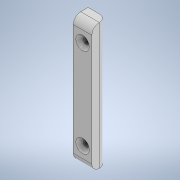
# Autodesk Inventor part: prindere_pusca_surub
Saved by Autodesk Inventor 2022.6 (Build 266554000, 554)
## iProperties
Created: 2026-11-05
Part Number: prindere_pusca_surub
Material: Generic
Document SubType Name: Modeling
Designer: Dragos Macovei
Density: 1 g/cm^3
Appearance: Default
Author: Dragos Macovei
Autodesk Inventor part; units mm, degrees
ref_plane "YZ Plane" through (0, 0, 0) normal (1, 0, 0) x (0, 1, 0)
ref_plane "XZ Plane" through (0, 0, 0) normal (0, 1, 0) x (-1, 0, 0)
ref_plane "XY Plane" through (0, 0, 0) normal (0, 0, 1) x (1, 0, 0)
sketch "Sketch1" plane through (0, 0, 0) normal (0, 1, 0) x (-1, 0, 0)
  line L0 (0, 0) -> (5, 0)
  line L1 (5, 0) -> (5, 4)
  line L2 (5, 4) -> (0, 4)
  line L3 (0, 4) -> (0, 0)
  dimension "d0" = 5
  dimension "d1" = 4
  constraints: 8 end point, 2 parallel, 1 horizontal, 1 perpendicular
  measures "d0" distance of L2.end L1.end
  measures "d1" distance of L1.end L0.end
extrude "Extrusion1" add sketch "Sketch1" along normal blind 34
sketch "Sketch2" plane through (-5, 0, 4) normal (0, 0, 1) x (1, 0, 0)
  line L0 (0, 0) -> (5, 0) projected
  line L1 (5, 0) -> (5, 34) projected
  line L2 (0, 34) -> (5, 34) projected
  line L3 (0, 0) -> (0, 34) projected
  line L4 (2.5, 40.1583) -> (2.5, -5.3866)
  circle A0 centre (2.5, 29) radius 0.8
  circle A1 centre (2.5, 5) radius 0.8
  dimension "d4" = 1.6
  dimension "d5" = 1.6
  dimension "d6" = 5
  dimension "d7" = 5
  constraints: 2 centre point, 2 end point, 2 point on line, 1 parallel
  measures "d4" diameter of A0
  measures "d5" diameter of A1
  measures "d6" distance from line of L0 A1.centre
  measures "d7" distance from line of L2 A0.centre
extrude "Extrusion2" cut sketch "Sketch2" against normal blind 34 contours A1 L4 | L4 A1 | A0 L4 | L4 A0
chamfer "Chamfer1" distance 1 angle 45 2 edges at (-3.3, 29, 4) (-3.3, 5, 4)
fillet "Fillet1" radius 2 3 edges at (-2.5, 34, 4) (-2.5, 0, 4) (0, 17, 0)
body "Solid1"
